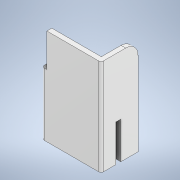
# Autodesk Inventor part: Tapa_prox_medio
Saved by Autodesk Inventor 2021 (Build 250183000, 183)
## iProperties
Created: 2026-04-06
Part Number: Tapa_prox_medio
Material: Plástico ABS
Document SubType Name: Modeling
Designer: thepr
Density: 1.06 g/cm^3
Appearance: Suave - Blanco
Mass: 4.55169 g
Surface Area: 42.3279 cm^2
Volume: 4.29404 cm^3
Author: thepr
## iProperties of the stored document _3DPrint.ipt
Created: 2026-05-24
Part Number: _3DPrint
Material: Genérico
Document SubType Name: Modeling
Designer: thepr
Density: 1 g/cm^3
Appearance: Valor por defecto
Author: thepr
Autodesk Inventor part; units mm, degrees
ref_plane "YZ Plane" through (0, 0, 0) normal (1, 0, 0) x (0, 1, 0)
ref_plane "XZ Plane" through (0, 0, 0) normal (0, 1, 0) x (-1, 0, 0)
ref_plane "XY Plane" through (0, 0, 0) normal (0, 0, 1) x (1, 0, 0)
sketch "Boceto1" plane through (0, 0, 0) normal (0, 0, 1) x (1, 0, 0)
  line L0 (0, 0) -> (24, 0)
  line L1 (24, 0) -> (24, 38)
  line L2 (24, 38) -> (0, 38)
  line L3 (0, 38) -> (0, 0)
  dimension "d0" = 24
  dimension "d1" = 38
  constraints: 8 end point, 2 parallel, 1 horizontal, 1 perpendicular
  measures "d0" distance between parallel lines of L1 L3
  measures "d1" distance of L2.end L0.start
extrude "Extrusión1" add sketch "Boceto1" along normal blind 2
sketch "Boceto2" plane through (0, 0, 0) normal (0, 0, -1) x (-1, 0, 0)
  line L0 (-24, 0) -> (-24, 38) projected
  line L1 (0, 0) -> (-24, 0) projected
  line L2 (0, 38) -> (0, 0) projected
  line L3 (-24, 38) -> (0, 38) projected
  line L4 (-24, 38) -> (0, 38) projected
  line L5 (-22, 38) -> (-22, 0)
  line L6 (-2, 38) -> (-2, 0)
  point P0 (-2, 38)
  dimension "d4" = 2
  dimension "d5" = 2
  constraints: 4 end point, 4 point on line, 2 perpendicular
  measures "d4" distance between parallel lines of L2 L6
  measures "d5" distance between parallel lines of L0 L5
extrude "Extrusión2" add sketch "Boceto2" along normal blind 13 contours L0 L3 L5 L1 | L6 L3 L2 L1
fillet "Empalme1" radius 4 2 edges at (0, 19, 2) (24, 19, 2)
sketch "Boceto3" plane through (24, 0, -13) normal (1, 0, 0) x (0, 0, -1)
  circle A0 centre (-5, 21.5) radius 2.5
  line L0 (0, 38) -> (-11, 38) projected
  line L1 (0, 38) -> (0, 0) projected
  line L2 (-5, 24) -> (0, 24)
  line L3 (0, 38) -> (0, 0) projected
  line L4 (-5, 19) -> (0, 19)
  point P0 (-13, 0)
  dimension "d9" = 5
  dimension "d10" = 16.5
  dimension "d11" = 5
  constraints: 4 end point, 2 point on circle, 2 tangent, 1 centre point, 1 midpoint, 1 perpendicular, 1 point on line
  measures "d9" diameter of A0
  measures "d10" distance from line of L0 A0.centre
  measures "d11" distance from line of L1 A0.centre
extrude "Extrusión3" [suppressed]
sketch "Boceto4" plane through (0, 0, 0) normal (0, 0, -1) x (-1, 0, 0)
  line L0 (-2, 0) -> (-2, 38) projected
  line L1 (-22, 38) -> (-2, 38) projected
  line L2 (-22, 38) -> (-22, 0) projected
  line L3 (-2, 0) -> (-22, 0) projected
  line L4 (-17, 38) -> (-17, 0)
  line L5 (-4, 0) -> (-20, 0) projected
  line L6 (-20, 38) -> (-4, 38) projected
  line L7 (-7, 38) -> (-7, 0)
  line L8 (-20, 38) -> (-20, 0) projected
  line L9 (-4, 0) -> (-4, 38) projected
  line L10 (-17, 3) -> (-7, 3)
  point P0 (0, 0)
  dimension "d14" = 10
  dimension "d15" = 3
  dimension "d18" = 3
  constraints: 6 end point, 6 point on line, 3 perpendicular
  measures "d14" distance between parallel lines of L7 L4
  measures "d15" distance between parallel lines of L4 L8
  measures "d18" distance between parallel lines of L3 L10
extrude "Extrusión4" add sketch "Boceto4" along normal blind 2 contours L7 L10 L4 L1
move faces "Desplazar1" translate (0, 0, -0.5) faces at (10.3333, 14.6667, -2)
sketch "Boceto5" plane through (24, 0, -13) normal (1, 0, 0) x (0, 0, -1)
  line L0 (-11, 0) -> (0, 0) projected
  line L1 (-9, 0) -> (-7, 0)
  line L2 (-7, 0) -> (-7, 15)
  line L3 (-7, 15) -> (-9, 15)
  line L4 (-9, 15) -> (-9, 0)
  point P0 (-13, 0)
  point P1 (-13, 38)
  dimension "d22" = 2
  dimension "d23" = 15
  dimension "d24" = 4
  constraints: 8 end point, 2 parallel, 1 horizontal, 1 perpendicular, 1 point on line
  measures "d22" distance of L2.end L3.end
  measures "d23" distance of L1.end L2.end
  measures "d24" distance from line of point (-13, 38) L4
extrude "Extrusión5" cut sketch "Boceto5" against normal blind 30
move faces "Desplazar2" translate (0, -0.5, 0) faces at (10.3333, 38, 1.3333)
sketch "Boceto6" plane through (17, 37.5, 0) normal (0, 1, 0) x (1, 0, 0)
  arc A0 (3, -2) -> (7, 2) centre (3, 2) ccw projected
  line L0 (7, 13) -> (7, 2) projected
  line L1 (5, 13) -> (7, 13) projected
  line L2 (5, 0) -> (5, 13) projected
  line L3 (5, 0) -> (0, 0) projected
  line L4 (0, 0) -> (0, 2.5) projected
  line L5 (-10, 2.5) -> (0, 2.5) projected
  line L6 (-10, 0) -> (-10, 2.5) projected
  line L7 (-10, 0) -> (-15, 0) projected
  line L8 (-15, 0) -> (-15, 13) projected
  line L9 (-17, 13) -> (-15, 13) projected
  line L10 (-17, 13) -> (-17, 2) projected
  arc A1 (-17, 2) -> (-13, -2) centre (-13, 2) ccw projected
  line L11 (3, -2) -> (-13, -2) projected
  point P0 (-17, 0)
extrude "Extrusión6" cut sketch "Boceto6" against normal blind 12
sketch "Boceto7" plane through (0, 0, -6) normal (-1, 0, 0) x (0, 0, 1)
  circle A0 centre (0.5, 6.5) radius 1.5
  line L0 (8, 0) -> (8, 25.5) projected
  line L1 (-1, 6.5) -> (-1, 0)
  line L2 (2, 15) -> (2, 0) projected
  line L3 (2, 6.5) -> (2, 0)
  line L4 (2, 0) -> (-1, 0)
  point P0 (6, 0)
  dimension "d32" = 3
  dimension "d33" = 7.5
  dimension "d34" = 6.5
  constraints: 6 end point, 2 point on circle, 1 centre point, 1 collinear, 1 perpendicular, 1 point on line, 1 tangent, 1 vertical
  measures "d32" diameter of A0
  measures "d33" distance from line of L0 A0.centre
  measures "d34" vertical distance of point (6, 0) A0.centre
extrude "Extrusión7" cut sketch "Boceto7" against normal blind 12
sketch "Boceto8" plane through (17, 25.5, 0) normal (0, 1, 0) x (1, 0, 0)
  arc A0 (-17, 2) -> (-13, -2) centre (-13, 2) ccw projected
  line L0 (3, -2) -> (-13, -2) projected
  arc A1 (3, -2) -> (7, 2) centre (3, 2) ccw projected
  line L1 (7, 13) -> (7, 2) projected
  line L2 (5, 13) -> (7, 13) projected
  line L3 (5, 0) -> (5, 13) projected
  line L4 (0, 0) -> (5, 0) projected
  line L5 (0, 2.5) -> (0, 0) projected
  line L6 (-10, 2.5) -> (0, 2.5) projected
  line L7 (-10, 0) -> (-10, 2.5) projected
  line L8 (-15, 0) -> (-10, 0) projected
  line L9 (-15, 13) -> (-15, 0) projected
  line L10 (-17, 13) -> (-15, 13) projected
  line L11 (-17, 2) -> (-17, 13) projected
  line L12 (0, 0) -> (-10, 0)
  line L13 (-15, 0) -> (5, 0) projected
  line L14 (-5, 0) -> (-5, 2.5)
  line L15 (1.9, 0) -> (-11.9, 0)
  line L16 (-11.9, 0) -> (-11.9, 2.5)
  line L17 (-11.9, 2.5) -> (1.9, 2.5)
  line L18 (1.9, 2.5) -> (1.9, 0)
  point P0 (-17, 0)
  dimension "d37" = 13.8
  dimension "d38" = 1.9
  constraints: 12 end point, 2 collinear, 2 midpoint, 2 parallel, 1 horizontal, 1 perpendicular, 1 point on line
  measures "d37" distance of L16.end L17.end
  measures "d38" distance between parallel lines of L18 L5
extrude "Extrusión8" add sketch "Boceto8" against normal up to surface (25.5 mm away) contours L16 L17 L7 L8 | L7 L6 L14 L12 | L14 L6 L5 L12 | L4 L5 L17 L18
sketch "Boceto9" plane through (17, 25.5, 0) normal (0, 1, 0) x (1, 0, 0)
  line L0 (-15, 0) -> (-11.9, 0) projected
  line L1 (-15, 13) -> (-15, 0) projected
  line L2 (-17, 13) -> (-15, 13) projected
  line L3 (-17, 2) -> (-17, 13) projected
  arc A0 (-17, 2) -> (-13, -2) centre (-13, 2) ccw projected
  line L4 (3, -2) -> (-13, -2) projected
  arc A1 (3, -2) -> (7, 2) centre (3, 2) ccw projected
  line L5 (7, 13) -> (7, 2) projected
  line L6 (5, 13) -> (7, 13) projected
  line L7 (5, 0) -> (5, 13) projected
  line L8 (1.9, 0) -> (5, 0) projected
  line L9 (1.9, 0) -> (1.9, 2.5) projected
  line L10 (1.9, 2.5) -> (-11.9, 2.5) projected
  line L11 (-11.9, 2.5) -> (-11.9, 0) projected
  line L12 (-15, 0) -> (-11.9, 0) projected
  line L13 (-15, 0) -> (-15, -1.4641)
  line L14 (-11.9, 0) -> (1.9, 0)
  point P0 (-17, 0)
  constraints: 4 end point, 1 collinear, 1 perpendicular, 1 point on circle
extrude "Extrusión9" add sketch "Boceto9" along normal blind 13.5 contours L0 L14 L8 L7 L6 L5 A1 L4 A0 L13
move faces "Desplazar3" translate (-0.1, 0, 0) faces at (2, 13.5, -10.6667)
move faces "Desplazar4" translate (0.1, 0, 0) faces at (22, 31, -6.3333)
sketch "Boceto10" plane through (0, 0, 2) normal (0, 0, 1) x (1, 0, 0)
  line L0 (4, 0) -> (4, 39) projected
  line L1 (4, 0) -> (20, 0) projected
  line L2 (20, 39) -> (20, 0) projected
  line L3 (4, 39) -> (20, 39) projected
  line L4 (20, 39) -> (20, 0) projected
  line L5 (20, 0) -> (24, 0) projected
  line L6 (24, 0) -> (24, 39) projected
  line L7 (20, 39) -> (24, 39) projected
  line L8 (2, 25.5) -> (0, 25.5) projected
  line L9 (0, 25.5) -> (0, 0) projected
  line L10 (0, 0) -> (4, 0) projected
  line L11 (4, 0) -> (4, 39) projected
  line L12 (2, 39) -> (4, 39) projected
  line L13 (2, 25.5) -> (2, 39) projected
  line L14 (1.9, 0) -> (1.9, 25.5) projected
  line L15 (22.1, 39) -> (22.1, 0) projected
extrude "Extrusión10" add sketch "Boceto10" against normal blind 1 contours L10 L14 L8 L13 L12 L0 | L2 L7 L15 L5
extrude "Extrusión11" add sketch "Boceto10" against normal blind 4 contours L10 L9 L8 L14 | L15 L7 L6 L5
fillet "Empalme2" radius 1 2 edges at (0, 12.75, 2) (24, 19.5, 2)
fillet "Empalme3" radius 5 2 edges at (0.95, 25.5, -13) (23.05, 39, -13)
move faces "Desplazar5" translate (0, 0, -0.15) faces at (0.6333, 10.2761, -6) (1.2667, 4.3333, -7)
